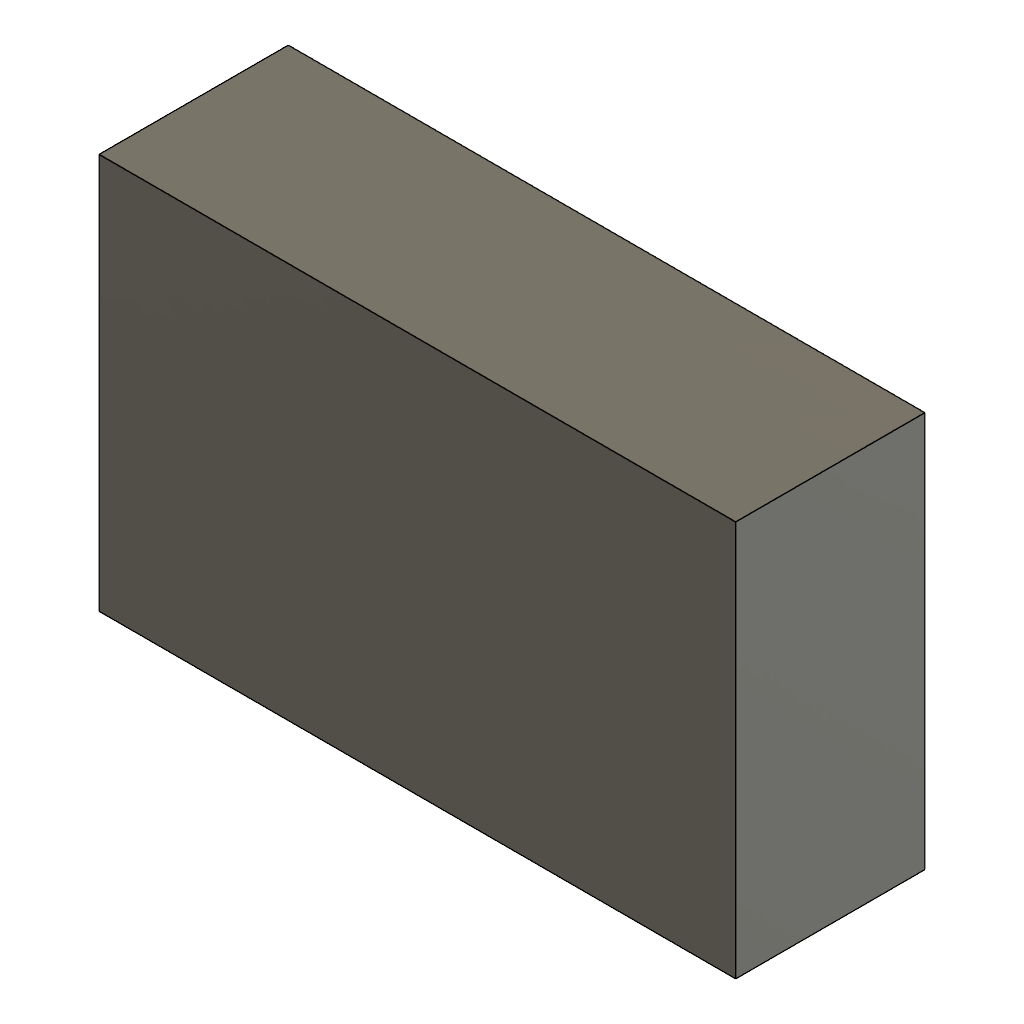
control-after (Autodesk Fusion 360 design; units mm, degrees)
part number: 2026-11-22-21-18-33-865
Autodesk Fusion 360 part; units mm, degrees
sketch "Sketch1" plane through (0, 0, 0) normal (0, 0, 1) x (1, 0, 0)
  line L0 (0, 0) -> (37, 0)
  line L1 (37, 0) -> (37, 23)
  line L2 (37, 23) -> (0, 23)
  line L3 (0, 23) -> (0, 0)
extrude "ControlledBoss" add sketch "Sketch1" along normal blind 11
